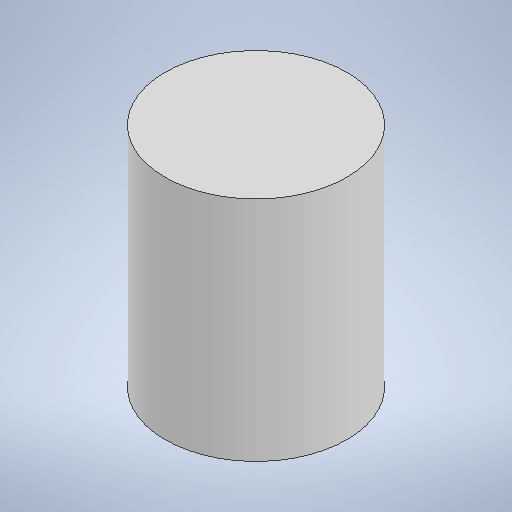
# Autodesk Inventor part: 轴1
Saved by Autodesk Inventor 2025 (Build 290162000, 162)
## iProperties
Created: 2026-11-18
Part Number: 轴1
Material: 常规
Document SubType Name: Modeling
Designer: ylh00
Density: 1 g/cm^3
Appearance: 默认
Author: ylh00
Autodesk Inventor part; units mm, degrees
ref_plane "YZ Plane" through (0, 0, 0) normal (1, 0, 0) x (0, 1, 0)
ref_plane "XZ Plane" through (0, 0, 0) normal (0, 1, 0) x (-1, 0, 0)
ref_plane "XY Plane" through (0, 0, 0) normal (0, 0, 1) x (1, 0, 0)
sketch "草图1" plane through (0, 0, 0) normal (0, 1, 0) x (-1, 0, 0)
  circle A0 centre (0, 0) radius 8
  dimension "d0" = 16
  constraints: 1 centre point, 1 coincident
  measures "d0" diameter of A0
extrude "拉伸1" add sketch "草图1" along normal blind 20
